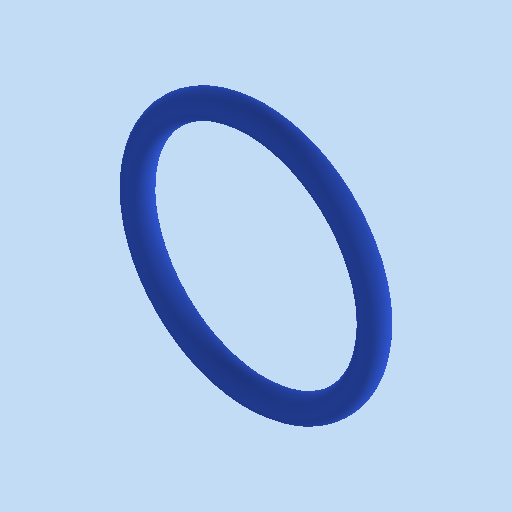
# Autodesk Inventor part: 90885__20250912
Saved by Autodesk Inventor 2023.3 (Build 273359000, 359)
## iProperties
Created: 2025-09-12
Part Number: 90885__20250912
Material: Generisch
Description: =<RBPARTNOTITLE2>
Document SubType Name: Modellieren
Designer: RIC7AN
Mass: 5.47171 g
Surface Area: 8.29047 cm^2
Volume: 0.621785 cm^3
Density: 8.8 g/cm^3
Sheet Metal Rule: Standard_mm
Appearance: blau AnP
Vendor: Geberit
RBPARTMADEOF: 90885
RBDRAWINGMISSINGSPEC: --
AnP_Kategorie: 2
RBPARTNOTITLE2: Geberit Mapress Dichtring FKM blau
RBSURFACE: --
RBPARTNOTITLE1: Geberit Mapress sealing FKM blue
AnP_Material: =<Material>
RBMATERIAL: --
RBMATNO: =<Part Number>
RBPARTNO: SIEHE MNR
Author: RIC7AN
Keywords: =<RBPARTMADEOF>
Comments: =<RBSURFACE2>
Revision Number: 01
Autodesk Inventor part; units mm, degrees
ref_plane "YZ Plane" through (0, 0, 0) normal (1, 0, 0) x (0, 1, 0)
ref_plane "XZ Plane" through (0, 0, 0) normal (0, 1, 0) x (-1, 0, 0)
ref_plane "XY Plane" through (0, 0, 0) normal (0, 0, 1) x (1, 0, 0)
sketch "Skizze1" plane through (0, 0, 0) normal (0, 0, 1) x (1, 0, 0)
  circle A0 centre (-14, 0) radius 1.5
  line L0 (0, 2.1) -> (0, -2.1) projected
  line L1 (-18.6, 0) -> (3.1, 0) projected
  point P0 (0, 0)
  dimension "d0" = 3
  dimension "d1" = 14
  constraints: 1 centre point, 1 point on line
  measures "d0" diameter of A0
  measures "d1" distance from line of L0 A0.centre
revolve "Umdrehung1" add sketch "Skizze1" angle 360 about axis through (0, 0, 0) along (0, -1, 0)
equation "\"Biegeradius\" = 1.5 * Stärke"
equation "\"BreiteBiegungsfreistellung\" = Stärke"
equation "\"TiefeBiegungsfreistellung\" = 0.5 * Stärke"
equation "\"GrößeEckenfreistellung\" = 4 * Stärke"
equation "\"MinimalRest\" = 2 * Stärke"
equation "\"Übergangsradius\" = Biegeradius"
equation "\"JacobiRadiusGröße\" = Biegeradius"
equation "\"Abstandsgröße\" = Stärke"
equation "\"Stärke\" = 0.5"
